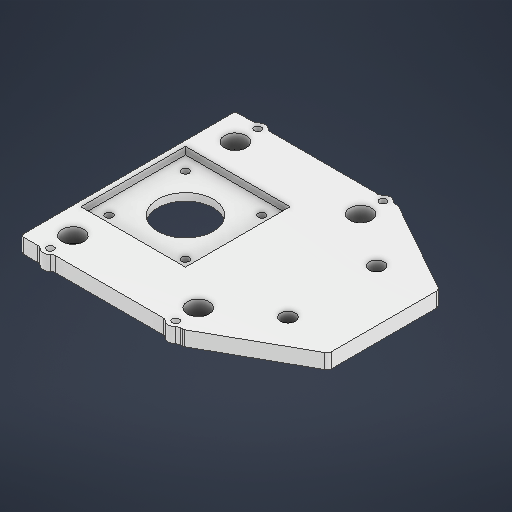
# Autodesk Inventor part: Крышка_для_оси_Z
Saved by Autodesk Inventor 2026 (Build 300175050, 175E)
## iProperties
Created: 2026-10-20
Part Number: Крышка_для_оси_Z
Material: Пластик АБС
Document SubType Name: Modeling
Designer: Ваня
Density: 1.06 g/cm^3
Appearance: Гладкий — белый
Author: Ваня
## iProperties of the stored document Крышка_для_оси_Z_3DПЕЧАТЬ.ipt
Created: 2026-11-07
Part Number: Крышка_для_оси_Z_3DПЕЧАТЬ
Material: Типовые
Document SubType Name: Modeling
Designer: VK7
Density: 1 g/cm^3
Appearance: По умолчанию
Author: VK7
Autodesk Inventor part; units mm, degrees
ref_plane "YZ Plane" through (0, 0, 0) normal (1, 0, 0) x (0, 1, 0)
ref_plane "XZ Plane" through (0, 0, 0) normal (0, 1, 0) x (-1, 0, 0)
ref_plane "РабПлоскость2" through (0, 56, 0) normal (0, 1, 0) x (1, 0, 0)
sketch "Эскиз9" plane through (0, 56, 0) normal (0, 1, 0) x (1, 0, 0)
  arc A0 (-38.1154, -88.6) -> (-37.6266, -88.4724) centre (-38.1154, -87.6) ccw projected
  line L0 (-37.6266, -88.4724) -> (-33.3354, -86.0681) projected
  arc A1 (-33.3354, -86.0681) -> (-33.4576, -85.6) centre (-33.4576, -85.85) ccw projected
  line L1 (-33.4576, -85.6) -> (-40.8417, -85.6) projected
  arc A2 (-41.3945, -85.4333) -> (-40.8417, -85.6) centre (-40.8417, -84.6) ccw projected
  arc A3 (-41.3945, -85.4333) -> (-43.6055, -85.4333) centre (-42.5, -87.1) ccw projected
  arc A4 (-44.1583, -85.6) -> (-43.6055, -85.4333) centre (-44.1583, -84.6) ccw projected
  line L2 (-44.1583, -85.6) -> (-91.7417, -85.6) projected
  arc A5 (-92.2945, -85.4333) -> (-91.7417, -85.6) centre (-91.7417, -84.6) ccw projected
  arc A6 (-92.2945, -85.4333) -> (-94.5055, -85.4333) centre (-93.4, -87.1) ccw projected
  arc A7 (-95.0583, -85.6) -> (-94.5055, -85.4333) centre (-95.0583, -84.6) ccw projected
  line L3 (-95.0583, -85.6) -> (-100, -85.6) projected
  arc A8 (-101, -84.6) -> (-100, -85.6) centre (-100, -84.6) ccw projected
  line L4 (-101, -84.6) -> (-101, -5.4) projected
  arc A9 (-100, -4.4) -> (-101, -5.4) centre (-100, -5.4) ccw projected
  line L5 (-100, -4.4) -> (-95.0583, -4.4) projected
  arc A10 (-94.5055, -4.5667) -> (-95.0583, -4.4) centre (-95.0583, -5.4) ccw projected
  arc A11 (-94.5055, -4.5667) -> (-92.2945, -4.5667) centre (-93.4, -2.9) ccw projected
  arc A12 (-91.7417, -4.4) -> (-92.2945, -4.5667) centre (-91.7417, -5.4) ccw projected
  line L6 (-91.7417, -4.4) -> (-44.1583, -4.4) projected
  arc A13 (-43.6055, -4.5667) -> (-44.1583, -4.4) centre (-44.1583, -5.4) ccw projected
  arc A14 (-43.6055, -4.5667) -> (-41.3945, -4.5667) centre (-42.5, -2.9) ccw projected
  arc A15 (-40.8417, -4.4) -> (-41.3945, -4.5667) centre (-40.8417, -5.4) ccw projected
  line L7 (-40.8417, -4.4) -> (-33.4576, -4.4) projected
  arc A16 (-33.4576, -4.4) -> (-33.3354, -3.9319) centre (-33.4576, -4.15) ccw projected
  line L8 (-33.3354, -3.9319) -> (-37.6266, -1.5276) projected
  arc A17 (-37.6266, -1.5276) -> (-38.1154, -1.4) centre (-38.1154, -2.4) ccw projected
  line L9 (-38.1154, -1.4) -> (-40.8417, -1.4) projected
  arc A18 (-41.3945, -1.2333) -> (-40.8417, -1.4) centre (-40.8417, -0.4) ccw projected
  arc A19 (-41.3945, -1.2333) -> (-43.6055, -1.2333) centre (-42.5, -2.9) ccw projected
  arc A20 (-44.1583, -1.4) -> (-43.6055, -1.2333) centre (-44.1583, -0.4) ccw projected
  line L10 (-44.1583, -1.4) -> (-91.7417, -1.4) projected
  arc A21 (-92.2945, -1.2333) -> (-91.7417, -1.4) centre (-91.7417, -0.4) ccw projected
  arc A22 (-92.2945, -1.2333) -> (-94.5055, -1.2333) centre (-93.4, -2.9) ccw projected
  arc A23 (-95.0583, -1.4) -> (-94.5055, -1.2333) centre (-95.0583, -0.4) ccw projected
  line L11 (-95.0583, -1.4) -> (-103, -1.4) projected
  arc A24 (-103, -1.4) -> (-104, -2.4) centre (-103, -2.4) ccw projected
  line L12 (-104, -2.4) -> (-104, -87.6) projected
  arc A25 (-104, -87.6) -> (-103, -88.6) centre (-103, -87.6) ccw projected
  line L13 (-103, -88.6) -> (-95.0583, -88.6) projected
  arc A26 (-94.5055, -88.7667) -> (-95.0583, -88.6) centre (-95.0583, -89.6) ccw projected
  arc A27 (-94.5055, -88.7667) -> (-92.2945, -88.7667) centre (-93.4, -87.1) ccw projected
  arc A28 (-91.7417, -88.6) -> (-92.2945, -88.7667) centre (-91.7417, -89.6) ccw projected
  line L14 (-91.7417, -88.6) -> (-44.1583, -88.6) projected
  arc A29 (-43.6055, -88.7667) -> (-44.1583, -88.6) centre (-44.1583, -89.6) ccw projected
  arc A30 (-43.6055, -88.7667) -> (-41.3945, -88.7667) centre (-42.5, -87.1) ccw projected
  arc A31 (-40.8417, -88.6) -> (-41.3945, -88.7667) centre (-40.8417, -89.6) ccw projected
  line L15 (-40.8417, -88.6) -> (-38.1154, -88.6) projected
  circle A32 centre (-93.4, -2.9) radius 1.425 projected
  circle A33 centre (-93.4, -87.1) radius 1.425 projected
  circle A34 centre (-42.5, -2.9) radius 1.425 projected
  circle A35 centre (-42.5, -87.1) radius 1.425 projected
  circle A36 centre (-5.5, -60.5) radius 1.5 projected
  circle A37 centre (-21, -45) radius 3 projected
  circle A38 centre (-49.4875, -50.75) radius 1.5 projected
  circle A39 centre (-60.9875, -50.75) radius 1.5 projected
  circle A40 centre (-55.2375, -45) radius 5.15 projected
  circle A41 centre (-49.4875, -39.25) radius 1.5 projected
  circle A42 centre (-60.9875, -39.25) radius 1.5 projected
  circle A43 centre (-5.5, -29.5) radius 1.5 projected
  circle A44 centre (-36.5, -29.5) radius 1.5 projected
  circle A45 centre (-36.5, -60.5) radius 1.5 projected
  arc A46 (0, -23.7816) -> (-1.0224, -22.0368) centre (-2, -23.7816) ccw projected
  line L16 (-1.0224, -22.0368) -> (-33.3354, -3.9319) projected
  arc A47 (-33.4576, -4.4) -> (-33.3354, -3.9319) centre (-33.4576, -4.15) ccw projected
  line L17 (-33.4576, -4.4) -> (-33.7, -4.4) projected
  arc A48 (-33.7, -4.4) -> (-34.5, -6) centre (-33.7, -5.4) ccw projected
  arc A49 (-50.5, -6) -> (-34.5, -6) centre (-42.5, -12) ccw projected
  arc A50 (-50.5, -6) -> (-51.3, -4.4) centre (-51.3, -5.4) ccw projected
  line L18 (-51.3, -4.4) -> (-84.6, -4.4) projected
  arc A51 (-84.6, -4.4) -> (-85.4, -6) centre (-84.6, -5.4) ccw projected
  arc A52 (-99.4, -20) -> (-85.4, -6) centre (-93.4, -12) ccw projected
  arc A53 (-99.4, -20) -> (-101, -20.8) centre (-100, -20.8) ccw projected
  line L19 (-101, -20.8) -> (-101, -69.2) projected
  arc A54 (-101, -69.2) -> (-99.4, -70) centre (-100, -69.2) ccw projected
  arc A55 (-85.4, -84) -> (-99.4, -70) centre (-93.4, -78) ccw projected
  arc A56 (-85.4, -84) -> (-84.6, -85.6) centre (-84.6, -84.6) ccw projected
  line L20 (-84.6, -85.6) -> (-51.3, -85.6) projected
  arc A57 (-51.3, -85.6) -> (-50.5, -84) centre (-51.3, -84.6) ccw projected
  arc A58 (-34.5, -84) -> (-50.5, -84) centre (-42.5, -78) ccw projected
  arc A59 (-34.5, -84) -> (-33.7, -85.6) centre (-33.7, -84.6) ccw projected
  line L21 (-33.7, -85.6) -> (-33.4576, -85.6) projected
  arc A60 (-33.3354, -86.0681) -> (-33.4576, -85.6) centre (-33.4576, -85.85) ccw projected
  line L22 (-33.3354, -86.0681) -> (-1.0224, -67.9632) projected
  arc A61 (-1.0224, -67.9632) -> (0, -66.2184) centre (-2, -66.2184) ccw projected
  line L23 (0, -66.2184) -> (0, -23.7816) projected
  line L24 (-101, -69.2) -> (-101, -78) projected
  arc A62 (-93.4, -85.6) -> (-101, -78) centre (-93.4, -78) ccw projected
  line L25 (-93.4, -85.6) -> (-84.6, -85.6) projected
  arc A63 (-85.4, -84) -> (-84.6, -85.6) centre (-84.6, -84.6) ccw projected
  arc A64 (-85.4, -84) -> (-99.4, -70) centre (-93.4, -78) ccw projected
  arc A65 (-101, -69.2) -> (-99.4, -70) centre (-100, -69.2) ccw projected
  arc A66 (-101, -84.6) -> (-100, -85.6) centre (-100, -84.6) ccw projected
  line L26 (-93.4, -85.6) -> (-100, -85.6) projected
  arc A67 (-101, -78) -> (-93.4, -85.6) centre (-93.4, -78) ccw projected
  line L27 (-101, -84.6) -> (-101, -78) projected
  circle A68 centre (-93.4, -78) radius 7.6 projected
  circle A69 centre (-93.4, -78) radius 4.2 projected
  arc A70 (-100, -4.4) -> (-101, -5.4) centre (-100, -5.4) ccw projected
  line L28 (-101, -5.4) -> (-101, -12) projected
  arc A71 (-93.4, -4.4) -> (-101, -12) centre (-93.4, -12) ccw projected
  line L29 (-100, -4.4) -> (-93.4, -4.4) projected
  circle A72 centre (-93.4, -12) radius 4.2 projected
  circle A73 centre (-93.4, -12) radius 7.6 projected
  line L30 (-42.5, -85.6) -> (-33.7, -85.6) projected
  arc A74 (-34.5, -84) -> (-33.7, -85.6) centre (-33.7, -84.6) ccw projected
  arc A75 (-34.5, -84) -> (-50.5, -84) centre (-42.5, -78) ccw projected
  arc A76 (-51.3, -85.6) -> (-50.5, -84) centre (-51.3, -84.6) ccw projected
  line L31 (-51.3, -85.6) -> (-42.5, -85.6) projected
  circle A77 centre (-42.5, -78) radius 7.6 projected
  circle A78 centre (-42.5, -78) radius 7.6 projected
  circle A79 centre (-42.5, -78) radius 4.2 projected
  circle A80 centre (-42.5, -12) radius 4.2 projected
  circle A81 centre (-42.5, -12) radius 7.6 projected
  line L32 (-42.5, -4.4) -> (-51.3, -4.4) projected
  arc A82 (-50.5, -6) -> (-51.3, -4.4) centre (-51.3, -5.4) ccw projected
  arc A83 (-50.5, -6) -> (-34.5, -6) centre (-42.5, -12) ccw projected
  arc A84 (-33.7, -4.4) -> (-34.5, -6) centre (-33.7, -5.4) ccw projected
  line L33 (-33.7, -4.4) -> (-42.5, -4.4) projected
  circle A85 centre (-42.5, -12) radius 7.6 projected
  point P0 (0, 0)
  point P1 (-33.3354, -3.9319)
  constraints: 2 vertical alignment
extrude "Выдавливание12" add sketch "Эскиз9" along normal blind 3 contours L15 A31 A30 A29 L14 A28 A27 A26 L13 A25 L12 A24 L11 A23 A22 A21 L10 A20 A19 A18 L9 A17 L8 A16 L7 L33 L32 L6 A12 A73 L29 L5 A9 L4 A8 L3 L26 L25 L2 L31 L30 L1 A1 L0 A0 | A1 L1 A59 A58 A57 L2 A56 A55 A54 L4 A53 A52 A51 L6 A50 A49 A48 L7 A16 L16 A46 L23 A61 L22 | L1 A2 A77 A4 L2 A57 A58 A59 | L30 A77 A2 | A77 A4 A3 A2 | A2 A3 A4 A77 | L31 A4 A77 | L2 A5 A62 L4 A54 A55 A56 | L25 A62 A5 | A48 A49 A50 L6 A13 A81 A15 L7 | A62 A67 A7 A6 A5 | A5 A6 A7 A67 A62 | L26 A7 A67 | A15 A81 L33 | L3 A8 L4 A67 A7 | A81 A13 A14 A15 | A15 A14 A13 A81 | A81 A13 L32 | L4 A73 A12 L6 A51 A52 A53 | L4 A9 L5 A10 A71 | A71 A10 A11 A12 A73 | A71 A73 A12 A11 A10 | A10 L29 A71 | A32 | A33 | A34 | A35 | A36 | A37 | A38 | A39 | A40 | A41 | A42 | A43 | A44 | A45 | A69 | A72 | A79 | A80
sketch "Эскиз10" plane through (0, 59, 0) normal (0, 1, 0) x (1, 0, 0)
  circle A0 centre (-42.5, -87.1) radius 1.425 projected
  circle A1 centre (-42.5, -87.1) radius 1.425
  circle A2 centre (-93.4, -87.1) radius 1.425 projected
  circle A3 centre (-93.4, -87.1) radius 1.425
  circle A4 centre (-93.4, -2.9) radius 1.425 projected
  circle A5 centre (-93.4, -2.9) radius 1.425
  circle A6 centre (-42.5, -2.9) radius 1.425 projected
  circle A7 centre (-42.5, -2.9) radius 1.425
  point P0 (0, 0)
  constraints: 4 centre point, 4 coincident
extrude "Выдавливание13" cut sketch "Эскиз10" against normal blind 3
sketch "Эскиз11" plane through (0, 59, 0) normal (0, 1, 0) x (1, 0, 0)
  circle A0 centre (-93.4, -87.1) radius 1.425 projected
  circle A1 centre (-93.4, -87.1) radius 3
  circle A2 centre (-42.5, -87.1) radius 1.425 projected
  circle A3 centre (-42.5, -87.1) radius 3
  circle A4 centre (-42.5, -2.9) radius 1.425 projected
  circle A5 centre (-42.5, -2.9) radius 3
  circle A6 centre (-93.4, -2.9) radius 1.425 projected
  circle A7 centre (-93.4, -2.9) radius 3
  point P0 (0, 0)
  dimension "d124" = 6
  dimension "d125" = 6
  dimension "d126" = 6
  dimension "d127" = 6
  constraints: 4 centre point, 4 coincident
  measures "d124" diameter of A1
  measures "d125" diameter of A3
  measures "d126" diameter of A5
  measures "d127" diameter of A7
extrude "Выдавливание14" add sketch "Эскиз11" against normal blind 3
fillet "Сопряжение11" radius 2 8 edges at (-39.9019, 57.5, 88.6) (-45.0981, 57.5, 88.6) (-90.8019, 57.5, 88.6) (-95.9981, 57.5, 88.6) (-95.9981, 57.5, 1.4) (-90.8019, 57.5, 1.4) (-45.0981, 57.5, 1.4) (-39.9019, 57.5, 1.4)
sketch "Эскиз12" plane through (0, 59, 0) normal (0, 1, 0) x (1, 0, 0)
  line L0 (0, -66.2184) -> (0, -23.7816) projected
  line L1 (0, -45) -> (-21, -45)
  line L2 (-21, -45) -> (-21, -60)
  line L3 (-21, -60) -> (-21, -63)
  circle A0 centre (-21, -63) radius 3
  circle A1 centre (-21, -27) radius 3
  point P0 (0, 0)
  dimension "d131" = 21
  dimension "d132" = 15
  dimension "d133" = 3
  constraints: 6 end point, 2 vertical, 1 centre point, 1 coincident, 1 horizontal, 1 midpoint, 1 symmetric about line, 1 vertical alignment, 3 other
  measures "d131" distance of L1.start L1.end
  measures "d132" distance of L1.end L2.end
  measures "d133" distance of L2.end L3.end
extrude "Выдавливание15" cut sketch "Эскиз12" against normal blind 3
sketch "Эскиз13" plane through (0, 59, 0) normal (0, 1, 0) x (1, 0, 0)
  line L0 (0, -45) -> (-21, -45) projected
  line L1 (-21, -45) -> (-82.5, -45)
  line L2 (-82.5, -45) -> (-104, -45)
  line L3 (-104, -2.4) -> (-104, -87.6) projected
  line L4 (-104, -45) -> (-101.65, -45)
  line L5 (-101.65, -45) -> (-96.15, -45)
  line L6 (-96.15, -45) -> (-96.15, -29.5)
  circle A0 centre (-96.15, -29.5) radius 1.5
  line L7 (-96.15, -45) -> (-80.65, -45)
  circle A1 centre (-96.15, -60.5) radius 1.5
  circle A2 centre (-65.15, -60.5) radius 1.5
  circle A3 centre (-65.15, -29.5) radius 1.5
  circle A4 centre (-80.65, -45) radius 11.3
  point P0 (0, 0)
  dimension "d136" = 61.5
  dimension "d137" = 2.35
  dimension "d138" = 5.5
  dimension "d139" = 15.5
  dimension "d140" = 3
  dimension "d141" = 15.5
  dimension "d144" = 360
  dimension "d146" = 22.6
  constraints: 12 end point, 5 centre point, 3 point on line, 2 coincident, 1 horizontal, 1 midpoint, 1 perpendicular, 9 other
  measures "d136" distance of L0.end L1.end
  measures "d137" distance of L2.end L4.end
  measures "d138" distance of L4.end L5.end
  measures "d139" distance of L5.end L6.end
  measures "d140" diameter of A0
  measures "d141" distance of L5.end L7.end
  measures "d146" diameter of A4
extrude "Выдавливание16" cut sketch "Эскиз13" against normal blind 3
sketch "Эскиз14" plane through (0, 59, 0) normal (0, 1, 0) x (1, 0, 0)
  line L0 (0, -45) -> (-21, -45) projected
  circle A0 centre (-93.4, -78) radius 4.2
  circle A1 centre (-93.4, -12) radius 4.2
  circle A2 centre (-42.5, -78) radius 4.2
  circle A3 centre (-21, -45) radius 3
  circle A4 centre (-42.5, -12) radius 4.2
  point P0 (0, 0)
  point P1 (40.8419, 49.1339)
  constraints: 5 centre point
extrude "Выдавливание17" cut sketch "Эскиз14" against normal blind 3 contours A0 | A1 | A2 | A4
sketch "Эскиз15" plane through (0, 59, 0) normal (0, 1, 0) x (1, 0, 0)
  line L0 (-101.9, -23.75) -> (-59.4, -23.75)
  line L1 (-59.4, -23.75) -> (-59.4, -66.25)
  line L2 (-59.4, -66.25) -> (-101.9, -66.25)
  line L3 (-101.9, -66.25) -> (-101.9, -23.75)
  circle A0 centre (-80.65, -45) radius 11.3 projected
  line L4 (-101.9, -23.75) -> (-59.4, -66.25) construction
  line L5 (-59.4, -23.75) -> (-101.9, -66.25) construction
  circle A1 centre (-42.5, -12) radius 4.2 projected
  circle A2 centre (-42.5, -78) radius 4.2 projected
  circle A3 centre (-93.4, -12) radius 4.2 projected
  circle A4 centre (-93.4, -78) radius 4.2 projected
  circle A5 centre (-65.15, -60.5) radius 1.5 projected
  circle A6 centre (-80.65, -45) radius 11.3 projected
  circle A7 centre (-96.15, -29.5) radius 1.5 projected
  circle A8 centre (-65.15, -29.5) radius 1.5 projected
  circle A9 centre (-96.15, -60.5) radius 1.5 projected
  circle A10 centre (-21, -27) radius 3 projected
  circle A11 centre (-21, -63) radius 3 projected
  line L6 (-96.9707, -1.4) -> (-103, -1.4) projected
  arc A12 (-103, -1.4) -> (-104, -2.4) centre (-103, -2.4) ccw projected
  line L7 (-104, -2.4) -> (-104, -87.6) projected
  arc A13 (-104, -87.6) -> (-103, -88.6) centre (-103, -87.6) ccw projected
  line L8 (-103, -88.6) -> (-96.9707, -88.6) projected
  arc A14 (-95.5424, -89.2) -> (-96.9707, -88.6) centre (-96.9707, -90.6) ccw projected
  arc A15 (-95.5424, -89.2) -> (-91.2576, -89.2) centre (-93.4, -87.1) ccw projected
  arc A16 (-89.8293, -88.6) -> (-91.2576, -89.2) centre (-89.8293, -90.6) ccw projected
  line L9 (-89.8293, -88.6) -> (-46.0707, -88.6) projected
  arc A17 (-44.6424, -89.2) -> (-46.0707, -88.6) centre (-46.0707, -90.6) ccw projected
  arc A18 (-44.6424, -89.2) -> (-40.3576, -89.2) centre (-42.5, -87.1) ccw projected
  arc A19 (-38.9293, -88.6) -> (-40.3576, -89.2) centre (-38.9293, -90.6) ccw projected
  line L10 (-38.9293, -88.6) -> (-38.1154, -88.6) projected
  arc A20 (-38.1154, -88.6) -> (-37.6266, -88.4724) centre (-38.1154, -87.6) ccw projected
  line L11 (-37.6266, -88.4724) -> (-1.0224, -67.9632) projected
  arc A21 (-1.0224, -67.9632) -> (0, -66.2184) centre (-2, -66.2184) ccw projected
  line L12 (0, -66.2184) -> (0, -23.7816) projected
  arc A22 (0, -23.7816) -> (-1.0224, -22.0368) centre (-2, -23.7816) ccw projected
  line L13 (-1.0224, -22.0368) -> (-37.6266, -1.5276) projected
  arc A23 (-37.6266, -1.5276) -> (-38.1154, -1.4) centre (-38.1154, -2.4) ccw projected
  line L14 (-38.1154, -1.4) -> (-38.9293, -1.4) projected
  arc A24 (-40.3576, -0.8) -> (-38.9293, -1.4) centre (-38.9293, 0.6) ccw projected
  arc A25 (-40.3576, -0.8) -> (-44.6424, -0.8) centre (-42.5, -2.9) ccw projected
  arc A26 (-46.0707, -1.4) -> (-44.6424, -0.8) centre (-46.0707, 0.6) ccw projected
  line L15 (-46.0707, -1.4) -> (-89.8293, -1.4) projected
  arc A27 (-91.2576, -0.8) -> (-89.8293, -1.4) centre (-89.8293, 0.6) ccw projected
  arc A28 (-91.2576, -0.8) -> (-95.5424, -0.8) centre (-93.4, -2.9) ccw projected
  arc A29 (-96.9707, -1.4) -> (-95.5424, -0.8) centre (-96.9707, 0.6) ccw projected
  circle A30 centre (-93.4, -2.9) radius 1.425 projected
  circle A31 centre (-93.4, -87.1) radius 1.425 projected
  circle A32 centre (-42.5, -2.9) radius 1.425 projected
  circle A33 centre (-42.5, -87.1) radius 1.425 projected
  point P0 (0, 0)
  dimension "d151" = 42.5
  dimension "d152" = 42.5
  constraints: 12 end point, 2 midpoint, 2 parallel, 1 horizontal, 1 perpendicular
  measures "d151" distance of L1.end L2.end
  measures "d152" distance of L0.end L1.end
extrude "Выдавливание18" add sketch "Эскиз15" along normal blind 3 contours A29 A28 A27 L15 A26 A25 A24 L14 A23 L13 A22 L12 A21 L11 A20 L10 A19 A18 A17 L9 A16 A15 A14 L8 A13 L7 A12 L6
offset faces "Размер1" outward -0.2 faces at (-38.3136, 61, 78.338) (-38.3136, 57, 78.338)
offset faces "Размер2" outward -0.2 faces at (-38.3136, 61, 12.338) (-38.3136, 57, 12.338)
offset faces "Размер3" outward -0.2 faces at (-89.2136, 61, 12.338) (-89.2136, 57, 12.338)
offset faces "Размер4" outward -0.2 faces at (-97.5456, 60, 77.3263) (-97.5456, 58, 77.3263)
